Autodesk Fusion 360 part; units mm, degrees
(part 3 of 8)
sketch "Rear removable beam panel | profile (2)" plane through (0, 0, -31) normal (0, 0, 1) x (1, 0, 0) in component "04 | Straight forearm beam"
  line L0 (45, -28) -> (105, -28)
  line L1 (105, -28) -> (108, -25)
  line L2 (108, -25) -> (108, 25)
  line L3 (108, 25) -> (105, 28)
  line L4 (105, 28) -> (45, 28)
  line L5 (45, 28) -> (42, 25)
  line L6 (42, 25) -> (42, -25)
  line L7 (42, -25) -> (45, -28)
  line L8 (55.7, -12) -> (55.725, -12.2536)
  line L9 (55.725, -12.2536) -> (55.799, -12.4975)
  line L10 (55.799, -12.4975) -> (55.9191, -12.7222)
  line L11 (55.9191, -12.7222) -> (56.0808, -12.9192)
  line L12 (56.0808, -12.9192) -> (56.2778, -13.0809)
  line L13 (56.2778, -13.0809) -> (56.5025, -13.201)
  line L14 (56.5025, -13.201) -> (56.7464, -13.275)
  line L15 (56.7464, -13.275) -> (57, -13.3)
  line L16 (57, -13.3) -> (63, -13.3)
  line L17 (63, -13.3) -> (63.2536, -13.275)
  line L18 (63.2536, -13.275) -> (63.4975, -13.201)
  line L19 (63.4975, -13.201) -> (63.7222, -13.0809)
  line L20 (63.7222, -13.0809) -> (63.9192, -12.9192)
  line L21 (63.9192, -12.9192) -> (64.0809, -12.7222)
  line L22 (64.0809, -12.7222) -> (64.201, -12.4975)
  line L23 (64.201, -12.4975) -> (64.275, -12.2536)
  line L24 (64.275, -12.2536) -> (64.3, -12)
  line L25 (64.3, -12) -> (64.275, -11.7464)
  line L26 (64.275, -11.7464) -> (64.201, -11.5025)
  line L27 (64.201, -11.5025) -> (64.0809, -11.2778)
  line L28 (64.0809, -11.2778) -> (63.9192, -11.0808)
  line L29 (63.9192, -11.0808) -> (63.7222, -10.9191)
  line L30 (63.7222, -10.9191) -> (63.4975, -10.799)
  line L31 (63.4975, -10.799) -> (63.2536, -10.725)
  line L32 (63.2536, -10.725) -> (63, -10.7)
  line L33 (63, -10.7) -> (57, -10.7)
  line L34 (57, -10.7) -> (56.7464, -10.725)
  line L35 (56.7464, -10.725) -> (56.5025, -10.799)
  line L36 (56.5025, -10.799) -> (56.2778, -10.9191)
  line L37 (56.2778, -10.9191) -> (56.0808, -11.0808)
  line L38 (56.0808, -11.0808) -> (55.9191, -11.2778)
  line L39 (55.9191, -11.2778) -> (55.799, -11.5025)
  line L40 (55.799, -11.5025) -> (55.725, -11.7464)
  line L41 (55.725, -11.7464) -> (55.7, -12)
  line L42 (55.7, 12) -> (55.725, 11.7464)
  line L43 (55.725, 11.7464) -> (55.799, 11.5025)
  line L44 (55.799, 11.5025) -> (55.9191, 11.2778)
  line L45 (55.9191, 11.2778) -> (56.0808, 11.0808)
  line L46 (56.0808, 11.0808) -> (56.2778, 10.9191)
  line L47 (56.2778, 10.9191) -> (56.5025, 10.799)
  line L48 (56.5025, 10.799) -> (56.7464, 10.725)
  line L49 (56.7464, 10.725) -> (57, 10.7)
  line L50 (57, 10.7) -> (63, 10.7)
  line L51 (63, 10.7) -> (63.2536, 10.725)
  line L52 (63.2536, 10.725) -> (63.4975, 10.799)
  line L53 (63.4975, 10.799) -> (63.7222, 10.9191)
  line L54 (63.7222, 10.9191) -> (63.9192, 11.0808)
  line L55 (63.9192, 11.0808) -> (64.0809, 11.2778)
  line L56 (64.0809, 11.2778) -> (64.201, 11.5025)
  line L57 (64.201, 11.5025) -> (64.275, 11.7464)
  line L58 (64.275, 11.7464) -> (64.3, 12)
  line L59 (64.3, 12) -> (64.275, 12.2536)
  line L60 (64.275, 12.2536) -> (64.201, 12.4975)
  line L61 (64.201, 12.4975) -> (64.0809, 12.7222)
  line L62 (64.0809, 12.7222) -> (63.9192, 12.9192)
  line L63 (63.9192, 12.9192) -> (63.7222, 13.0809)
  line L64 (63.7222, 13.0809) -> (63.4975, 13.201)
  line L65 (63.4975, 13.201) -> (63.2536, 13.275)
  line L66 (63.2536, 13.275) -> (63, 13.3)
  line L67 (63, 13.3) -> (57, 13.3)
  line L68 (57, 13.3) -> (56.7464, 13.275)
  line L69 (56.7464, 13.275) -> (56.5025, 13.201)
  line L70 (56.5025, 13.201) -> (56.2778, 13.0809)
  line L71 (56.2778, 13.0809) -> (56.0808, 12.9192)
  line L72 (56.0808, 12.9192) -> (55.9191, 12.7222)
  line L73 (55.9191, 12.7222) -> (55.799, 12.4975)
  line L74 (55.799, 12.4975) -> (55.725, 12.2536)
  line L75 (55.725, 12.2536) -> (55.7, 12)
  line L76 (64.7, -12) -> (64.725, -12.2536)
  line L77 (64.725, -12.2536) -> (64.799, -12.4975)
  line L78 (64.799, -12.4975) -> (64.9191, -12.7222)
  line L79 (64.9191, -12.7222) -> (65.0808, -12.9192)
  line L80 (65.0808, -12.9192) -> (65.2778, -13.0809)
  line L81 (65.2778, -13.0809) -> (65.5025, -13.201)
  line L82 (65.5025, -13.201) -> (65.7464, -13.275)
  line L83 (65.7464, -13.275) -> (66, -13.3)
  line L84 (66, -13.3) -> (72, -13.3)
  line L85 (72, -13.3) -> (72.2536, -13.275)
  line L86 (72.2536, -13.275) -> (72.4975, -13.201)
  line L87 (72.4975, -13.201) -> (72.7222, -13.0809)
  line L88 (72.7222, -13.0809) -> (72.9192, -12.9192)
  line L89 (72.9192, -12.9192) -> (73.0809, -12.7222)
  line L90 (73.0809, -12.7222) -> (73.201, -12.4975)
  line L91 (73.201, -12.4975) -> (73.275, -12.2536)
  line L92 (73.275, -12.2536) -> (73.3, -12)
  line L93 (73.3, -12) -> (73.275, -11.7464)
  line L94 (73.275, -11.7464) -> (73.201, -11.5025)
  line L95 (73.201, -11.5025) -> (73.0809, -11.2778)
  line L96 (73.0809, -11.2778) -> (72.9192, -11.0808)
  line L97 (72.9192, -11.0808) -> (72.7222, -10.9191)
  line L98 (72.7222, -10.9191) -> (72.4975, -10.799)
  line L99 (72.4975, -10.799) -> (72.2536, -10.725)
  line L100 (72.2536, -10.725) -> (72, -10.7)
  line L101 (72, -10.7) -> (66, -10.7)
  line L102 (66, -10.7) -> (65.7464, -10.725)
  line L103 (65.7464, -10.725) -> (65.5025, -10.799)
  line L104 (65.5025, -10.799) -> (65.2778, -10.9191)
  line L105 (65.2778, -10.9191) -> (65.0808, -11.0808)
  line L106 (65.0808, -11.0808) -> (64.9191, -11.2778)
  line L107 (64.9191, -11.2778) -> (64.799, -11.5025)
  line L108 (64.799, -11.5025) -> (64.725, -11.7464)
  line L109 (64.725, -11.7464) -> (64.7, -12)
  line L110 (64.7, 12) -> (64.725, 11.7464)
  line L111 (64.725, 11.7464) -> (64.799, 11.5025)
  line L112 (64.799, 11.5025) -> (64.9191, 11.2778)
  line L113 (64.9191, 11.2778) -> (65.0808, 11.0808)
  line L114 (65.0808, 11.0808) -> (65.2778, 10.9191)
  line L115 (65.2778, 10.9191) -> (65.5025, 10.799)
  line L116 (65.5025, 10.799) -> (65.7464, 10.725)
  line L117 (65.7464, 10.725) -> (66, 10.7)
  line L118 (66, 10.7) -> (72, 10.7)
  line L119 (72, 10.7) -> (72.2536, 10.725)
  line L120 (72.2536, 10.725) -> (72.4975, 10.799)
  line L121 (72.4975, 10.799) -> (72.7222, 10.9191)
  line L122 (72.7222, 10.9191) -> (72.9192, 11.0808)
  line L123 (72.9192, 11.0808) -> (73.0809, 11.2778)
  line L124 (73.0809, 11.2778) -> (73.201, 11.5025)
  line L125 (73.201, 11.5025) -> (73.275, 11.7464)
  line L126 (73.275, 11.7464) -> (73.3, 12)
  line L127 (73.3, 12) -> (73.275, 12.2536)
  line L128 (73.275, 12.2536) -> (73.201, 12.4975)
  line L129 (73.201, 12.4975) -> (73.0809, 12.7222)
  line L130 (73.0809, 12.7222) -> (72.9192, 12.9192)
  line L131 (72.9192, 12.9192) -> (72.7222, 13.0809)
  line L132 (72.7222, 13.0809) -> (72.4975, 13.201)
  line L133 (72.4975, 13.201) -> (72.2536, 13.275)
  line L134 (72.2536, 13.275) -> (72, 13.3)
  line L135 (72, 13.3) -> (66, 13.3)
  line L136 (66, 13.3) -> (65.7464, 13.275)
  line L137 (65.7464, 13.275) -> (65.5025, 13.201)
  line L138 (65.5025, 13.201) -> (65.2778, 13.0809)
  line L139 (65.2778, 13.0809) -> (65.0808, 12.9192)
  line L140 (65.0808, 12.9192) -> (64.9191, 12.7222)
  line L141 (64.9191, 12.7222) -> (64.799, 12.4975)
  line L142 (64.799, 12.4975) -> (64.725, 12.2536)
  line L143 (64.725, 12.2536) -> (64.7, 12)
  line L144 (73.7, -12) -> (73.725, -12.2536)
  line L145 (73.725, -12.2536) -> (73.799, -12.4975)
  line L146 (73.799, -12.4975) -> (73.9191, -12.7222)
  line L147 (73.9191, -12.7222) -> (74.0808, -12.9192)
  line L148 (74.0808, -12.9192) -> (74.2778, -13.0809)
  line L149 (74.2778, -13.0809) -> (74.5025, -13.201)
  line L150 (74.5025, -13.201) -> (74.7464, -13.275)
  line L151 (74.7464, -13.275) -> (75, -13.3)
  line L152 (75, -13.3) -> (81, -13.3)
  line L153 (81, -13.3) -> (81.2536, -13.275)
  line L154 (81.2536, -13.275) -> (81.4975, -13.201)
  line L155 (81.4975, -13.201) -> (81.7222, -13.0809)
  line L156 (81.7222, -13.0809) -> (81.9192, -12.9192)
  line L157 (81.9192, -12.9192) -> (82.0809, -12.7222)
  line L158 (82.0809, -12.7222) -> (82.201, -12.4975)
  line L159 (82.201, -12.4975) -> (82.275, -12.2536)
  line L160 (82.275, -12.2536) -> (82.3, -12)
  line L161 (82.3, -12) -> (82.275, -11.7464)
  line L162 (82.275, -11.7464) -> (82.201, -11.5025)
  line L163 (82.201, -11.5025) -> (82.0809, -11.2778)
  line L164 (82.0809, -11.2778) -> (81.9192, -11.0808)
  line L165 (81.9192, -11.0808) -> (81.7222, -10.9191)
  line L166 (81.7222, -10.9191) -> (81.4975, -10.799)
  line L167 (81.4975, -10.799) -> (81.2536, -10.725)
  line L168 (81.2536, -10.725) -> (81, -10.7)
  line L169 (81, -10.7) -> (75, -10.7)
  line L170 (75, -10.7) -> (74.7464, -10.725)
  line L171 (74.7464, -10.725) -> (74.5025, -10.799)
  line L172 (74.5025, -10.799) -> (74.2778, -10.9191)
  line L173 (74.2778, -10.9191) -> (74.0808, -11.0808)
  line L174 (74.0808, -11.0808) -> (73.9191, -11.2778)
  line L175 (73.9191, -11.2778) -> (73.799, -11.5025)
  line L176 (73.799, -11.5025) -> (73.725, -11.7464)
  line L177 (73.725, -11.7464) -> (73.7, -12)
  line L178 (73.7, 12) -> (73.725, 11.7464)
  line L179 (73.725, 11.7464) -> (73.799, 11.5025)
  line L180 (73.799, 11.5025) -> (73.9191, 11.2778)
  line L181 (73.9191, 11.2778) -> (74.0808, 11.0808)
  line L182 (74.0808, 11.0808) -> (74.2778, 10.9191)
  line L183 (74.2778, 10.9191) -> (74.5025, 10.799)
  line L184 (74.5025, 10.799) -> (74.7464, 10.725)
  line L185 (74.7464, 10.725) -> (75, 10.7)
  line L186 (75, 10.7) -> (81, 10.7)
  line L187 (81, 10.7) -> (81.2536, 10.725)
  line L188 (81.2536, 10.725) -> (81.4975, 10.799)
  line L189 (81.4975, 10.799) -> (81.7222, 10.9191)
  line L190 (81.7222, 10.9191) -> (81.9192, 11.0808)
  line L191 (81.9192, 11.0808) -> (82.0809, 11.2778)
  line L192 (82.0809, 11.2778) -> (82.201, 11.5025)
  line L193 (82.201, 11.5025) -> (82.275, 11.7464)
  line L194 (82.275, 11.7464) -> (82.3, 12)
  line L195 (82.3, 12) -> (82.275, 12.2536)
  line L196 (82.275, 12.2536) -> (82.201, 12.4975)
  line L197 (82.201, 12.4975) -> (82.0809, 12.7222)
  line L198 (82.0809, 12.7222) -> (81.9192, 12.9192)
  line L199 (81.9192, 12.9192) -> (81.7222, 13.0809)
  line L200 (81.7222, 13.0809) -> (81.4975, 13.201)
  line L201 (81.4975, 13.201) -> (81.2536, 13.275)
  line L202 (81.2536, 13.275) -> (81, 13.3)
  line L203 (81, 13.3) -> (75, 13.3)
  line L204 (75, 13.3) -> (74.7464, 13.275)
  line L205 (74.7464, 13.275) -> (74.5025, 13.201)
  line L206 (74.5025, 13.201) -> (74.2778, 13.0809)
  line L207 (74.2778, 13.0809) -> (74.0808, 12.9192)
  line L208 (74.0808, 12.9192) -> (73.9191, 12.7222)
  line L209 (73.9191, 12.7222) -> (73.799, 12.4975)
  line L210 (73.799, 12.4975) -> (73.725, 12.2536)
  line L211 (73.725, 12.2536) -> (73.7, 12)
extrude "Rear removable beam panel'" add sketch "Rear removable beam panel | profile (2)" along normal blind 2.5 separate body makes body 95 in component "04 | Straight forearm beam"
ref_plane "WorkPlane4" through (0, 0, 39.5) normal (0, 0, 1) x (1, 0, 0) in component "04 | Straight forearm beam"
sketch "Front removable beam panel | profile (2)" plane through (0, 0, 39.5) normal (0, 0, 1) x (1, 0, 0) in component "04 | Straight forearm beam"
  line L0 (45, -28) -> (105, -28)
  line L1 (105, -28) -> (108, -25)
  line L2 (108, -25) -> (108, 25)
  line L3 (108, 25) -> (105, 28)
  line L4 (105, 28) -> (45, 28)
  line L5 (45, 28) -> (42, 25)
  line L6 (42, 25) -> (42, -25)
  line L7 (42, -25) -> (45, -28)
extrude "Front removable beam panel'" add sketch "Front removable beam panel | profile (2)" along normal blind 2.5 separate body makes body 96 in component "04 | Straight forearm beam"
ref_plane "WorkPlane5" through (0, 0, 14) normal (0, 0, 1) x (1, 0, 0) in component "04 | Straight forearm beam"
sketch "Motor mount | metal, stock and holes to finalize | profile (4)" plane through (0, 0, 14) normal (0, 0, 1) x (1, 0, 0) in component "04 | Straight forearm beam"
  line L0 (46.35, -23.65) -> (91.65, -23.65)
  line L1 (91.65, -23.65) -> (92.65, -22.65)
  line L2 (92.65, -22.65) -> (92.65, 22.65)
  line L3 (92.65, 22.65) -> (91.65, 23.65)
  line L4 (91.65, 23.65) -> (46.35, 23.65)
  line L5 (46.35, 23.65) -> (45.35, 22.65)
  line L6 (45.35, 22.65) -> (45.35, -22.65)
  line L7 (45.35, -22.65) -> (46.35, -23.65)
  circle A0 centre (69, 0) radius 11.2
  circle A1 centre (53.5, -15.5) radius 1.6
  circle A2 centre (53.5, 15.5) radius 1.6
  circle A3 centre (84.5, -15.5) radius 1.6
  circle A4 centre (84.5, 15.5) radius 1.6
extrude "Motor mount | metal, stock and holes to finalize'''" add sketch "Motor mount | metal, stock and holes to finalize | profile (4)" along normal blind 3 separate body makes body 97 in component "04 | Straight forearm beam"
ref_plane "WorkPlane6" through (0, 0, -36) normal (0, 0, 1) x (1, 0, 0) in component "04 | Straight forearm beam"
sketch "Proximal bearing cheek | profile (2)" plane through (0, 0, -36) normal (0, 0, 1) x (1, 0, 0) in component "04 | Straight forearm beam"
  line L0 (-40, 0) -> (-39.6578, -5.221)
  line L1 (-39.6578, -5.221) -> (-38.637, -10.3528)
  line L2 (-38.637, -10.3528) -> (-36.9552, -15.3073)
  line L3 (-36.9552, -15.3073) -> (-34.641, -20)
  line L4 (-34.641, -20) -> (-31.7341, -24.3505)
  line L5 (-31.7341, -24.3505) -> (-28.2843, -28.2843)
  line L6 (-28.2843, -28.2843) -> (-24.3505, -31.7341)
  line L7 (-24.3505, -31.7341) -> (-20, -34.641)
  line L8 (-20, -34.641) -> (-15.3073, -36.9552)
  line L9 (-15.3073, -36.9552) -> (-10.3528, -38.637)
  line L10 (-10.3528, -38.637) -> (-5.221, -39.6578)
  line L11 (-5.221, -39.6578) -> (0, -40)
  line L12 (0, -40) -> (5.221, -39.6578)
  line L13 (5.221, -39.6578) -> (10.3528, -38.637)
  line L14 (10.3528, -38.637) -> (59, -23)
  line L15 (59, -23) -> (59, 23)
  line L16 (59, 23) -> (10.3528, 38.637)
  line L17 (10.3528, 38.637) -> (5.221, 39.6578)
  line L18 (5.221, 39.6578) -> (0, 40)
  line L19 (0, 40) -> (-5.221, 39.6578)
  line L20 (-5.221, 39.6578) -> (-10.3528, 38.637)
  line L21 (-10.3528, 38.637) -> (-15.3073, 36.9552)
  line L22 (-15.3073, 36.9552) -> (-20, 34.641)
  line L23 (-20, 34.641) -> (-24.3505, 31.7341)
  line L24 (-24.3505, 31.7341) -> (-28.2843, 28.2843)
  line L25 (-28.2843, 28.2843) -> (-31.7341, 24.3505)
  line L26 (-31.7341, 24.3505) -> (-34.641, 20)
  line L27 (-34.641, 20) -> (-36.9552, 15.3073)
  line L28 (-36.9552, 15.3073) -> (-38.637, 10.3528)
  line L29 (-38.637, 10.3528) -> (-39.6578, 5.221)
  line L30 (-39.6578, 5.221) -> (-40, 0)
  circle A0 centre (0, 0) radius 15.15
extrude "Proximal bearing cheek'" add sketch "Proximal bearing cheek | profile (2)" along normal blind 5 separate body makes body 98 in component "04 | Straight forearm beam"
ref_plane "WorkPlane7" through (0, 0, 42) normal (0, 0, 1) x (1, 0, 0) in component "04 | Straight forearm beam"
sketch "Proximal bearing cheek | profile (1) (2)" plane through (0, 0, 42) normal (0, 0, 1) x (1, 0, 0) in component "04 | Straight forearm beam"
  line L0 (-40, 0) -> (-39.6578, -5.221)
  line L1 (-39.6578, -5.221) -> (-38.637, -10.3528)
  line L2 (-38.637, -10.3528) -> (-36.9552, -15.3073)
  line L3 (-36.9552, -15.3073) -> (-34.641, -20)
  line L4 (-34.641, -20) -> (-31.7341, -24.3505)
  line L5 (-31.7341, -24.3505) -> (-28.2843, -28.2843)
  line L6 (-28.2843, -28.2843) -> (-24.3505, -31.7341)
  line L7 (-24.3505, -31.7341) -> (-20, -34.641)
  line L8 (-20, -34.641) -> (-15.3073, -36.9552)
  line L9 (-15.3073, -36.9552) -> (-10.3528, -38.637)
  line L10 (-10.3528, -38.637) -> (-5.221, -39.6578)
  line L11 (-5.221, -39.6578) -> (0, -40)
  line L12 (0, -40) -> (5.221, -39.6578)
  line L13 (5.221, -39.6578) -> (10.3528, -38.637)
  line L14 (10.3528, -38.637) -> (59, -23)
  line L15 (59, -23) -> (59, 23)
  line L16 (59, 23) -> (10.3528, 38.637)
  line L17 (10.3528, 38.637) -> (5.221, 39.6578)
  line L18 (5.221, 39.6578) -> (0, 40)
  line L19 (0, 40) -> (-5.221, 39.6578)
  line L20 (-5.221, 39.6578) -> (-10.3528, 38.637)
  line L21 (-10.3528, 38.637) -> (-15.3073, 36.9552)
  line L22 (-15.3073, 36.9552) -> (-20, 34.641)
  line L23 (-20, 34.641) -> (-24.3505, 31.7341)
  line L24 (-24.3505, 31.7341) -> (-28.2843, 28.2843)
  line L25 (-28.2843, 28.2843) -> (-31.7341, 24.3505)
  line L26 (-31.7341, 24.3505) -> (-34.641, 20)
  line L27 (-34.641, 20) -> (-36.9552, 15.3073)
  line L28 (-36.9552, 15.3073) -> (-38.637, 10.3528)
  line L29 (-38.637, 10.3528) -> (-39.6578, 5.221)
  line L30 (-39.6578, 5.221) -> (-40, 0)
  circle A0 centre (0, 0) radius 15.15
extrude "Proximal bearing cheek (1)'" add sketch "Proximal bearing cheek | profile (1) (2)" along normal blind 5 separate body makes body 99 in component "04 | Straight forearm beam"
ref_plane "WorkPlane8" through (0, 0, 20) normal (0, 0, 1) x (1, 0, 0) in component "04 | Straight forearm beam"
sketch "20T pulley envelope | tooth profile pending | profile (4)" plane through (0, 0, 20) normal (0, 0, 1) x (1, 0, 0) in component "04 | Straight forearm beam"
  circle A0 centre (69, 0) radius 6.9662
  circle A1 centre (69, 0) radius 2.5
extrude "20T pulley envelope | tooth profile pending'''" add sketch "20T pulley envelope | tooth profile pending | profile (4)" along normal blind 6 separate body makes body 100 in component "04 | Straight forearm beam"
ref_plane "WorkPlane9" through (0, 0, 26) normal (0, 0, 1) x (1, 0, 0) in component "04 | Straight forearm beam"
sketch "20T flange | profile (4)" plane through (0, 0, 26) normal (0, 0, 1) x (1, 0, 0) in component "04 | Straight forearm beam"
  circle A0 centre (69, 0) radius 7.3662
  circle A1 centre (69, 0) radius 2.5
extrude "20T flange'''" add sketch "20T flange | profile (4)" along normal blind 0.8 separate body makes body 101 in component "04 | Straight forearm beam"
ref_plane "WorkPlane10" through (0, 0, 20) normal (0, 0, 1) x (1, 0, 0) in component "04 | Straight forearm beam"
sketch "80T pulley envelope | tooth profile pending | profile" plane through (0, 0, 20) normal (0, 0, 1) x (1, 0, 0) in component "04 | Straight forearm beam"
  circle A0 centre (155, 0) radius 26.0648
  circle A1 centre (155, 0) radius 6
extrude "80T pulley envelope | tooth profile pending" add sketch "80T pulley envelope | tooth profile pending | profile" along normal blind 6 separate body makes body 102 in component "04 | Straight forearm beam"
ref_plane "WorkPlane11" through (0, 0, 26) normal (0, 0, 1) x (1, 0, 0) in component "04 | Straight forearm beam"
sketch "80T flange | profile" plane through (0, 0, 26) normal (0, 0, 1) x (1, 0, 0) in component "04 | Straight forearm beam"
  circle A0 centre (155, 0) radius 26.4648
  circle A1 centre (155, 0) radius 6
extrude "80T flange" add sketch "80T flange | profile" along normal blind 0.8 separate body makes body 103 in component "04 | Straight forearm beam"
ref_plane "WorkPlane12" through (0, 0, 20) normal (0, 0, 1) x (1, 0, 0) in component "04 | Straight forearm beam"
sketch "Internal 4:1 span | belt length pending | profile" plane through (0, 0, 20) normal (0, 0, 1) x (1, 0, 0) in component "04 | Straight forearm beam"
  line L0 (67.4419, 6.841) -> (149.2005, 25.4627)
  line L1 (149.2005, 25.4627) -> (149.4892, 24.1951)
  line L2 (149.4892, 24.1951) -> (67.7306, 5.5735)
  line L3 (67.7306, 5.5735) -> (67.4419, 6.841)
extrude "Internal 4:1 span | belt length pending" add sketch "Internal 4:1 span | belt length pending | profile" along normal blind 6 separate body makes body 104 in component "04 | Straight forearm beam"
ref_plane "WorkPlane13" through (0, 0, 20) normal (0, 0, 1) x (1, 0, 0) in component "04 | Straight forearm beam"
sketch "Internal 4:1 span | belt length pending | profile (1)" plane through (0, 0, 20) normal (0, 0, 1) x (1, 0, 0) in component "04 | Straight forearm beam"
  line L0 (67.7306, -5.5735) -> (149.4892, -24.1951)
  line L1 (149.4892, -24.1951) -> (149.2005, -25.4627)
  line L2 (149.2005, -25.4627) -> (67.4419, -6.841)
  line L3 (67.4419, -6.841) -> (67.7306, -5.5735)
extrude "Internal 4:1 span | belt length pending (1)" add sketch "Internal 4:1 span | belt length pending | profile (1)" along normal blind 6 separate body makes body 105 in component "04 | Straight forearm beam"
ref_plane "WorkPlane14" through (0, 0, 20) normal (0, 0, 1) x (1, 0, 0) in component "04 | Straight forearm beam"
sketch "Internal 4:1 drive wrap | profile" plane through (0, 0, 20) normal (0, 0, 1) x (1, 0, 0) in component "04 | Straight forearm beam"
  circle A0 centre (69, 0) radius 7.0162
  circle A1 centre (69, 0) radius 5.7162
extrude "Internal 4:1 drive wrap" add sketch "Internal 4:1 drive wrap | profile" along normal blind 6 separate body makes body 106 in component "04 | Straight forearm beam"
ref_plane "WorkPlane15" through (0, 0, 20) normal (0, 0, 1) x (1, 0, 0) in component "04 | Straight forearm beam"
sketch "Internal 4:1 driven wrap | profile" plane through (0, 0, 20) normal (0, 0, 1) x (1, 0, 0) in component "04 | Straight forearm beam"
  circle A0 centre (155, 0) radius 26.1148
  circle A1 centre (155, 0) radius 24.8148
extrude "Internal 4:1 driven wrap" add sketch "Internal 4:1 driven wrap | profile" along normal blind 6 separate body makes body 107 in component "04 | Straight forearm beam"
ref_plane "WorkPlane16" through (0, 0, -36) normal (0, 0, 1) x (1, 0, 0) in component "04 | Straight forearm beam"
sketch "Distal flat fork cheek | profile (2)" plane through (0, 0, -36) normal (0, 0, 1) x (1, 0, 0) in component "04 | Straight forearm beam"
  line L0 (98, -23) -> (150.8232, -31.7262)
  line L1 (150.8232, -31.7262) -> (155, -32)
  line L2 (155, -32) -> (159.1768, -31.7262)
  line L3 (159.1768, -31.7262) -> (163.2822, -30.9096)
  line L4 (163.2822, -30.9096) -> (167.2459, -29.5641)
  line L5 (167.2459, -29.5641) -> (171, -27.7128)
  line L6 (171, -27.7128) -> (174.4804, -25.3873)
  line L7 (174.4804, -25.3873) -> (177.6274, -22.6274)
  line L8 (177.6274, -22.6274) -> (180.3873, -19.4804)
  line L9 (180.3873, -19.4804) -> (182.7128, -16)
  line L10 (182.7128, -16) -> (184.5641, -12.2459)
  line L11 (184.5641, -12.2459) -> (185.9096, -8.2822)
  line L12 (185.9096, -8.2822) -> (186.7262, -4.1768)
  line L13 (186.7262, -4.1768) -> (187, 0)
  line L14 (187, 0) -> (186.7262, 4.1768)
  line L15 (186.7262, 4.1768) -> (185.9096, 8.2822)
  line L16 (185.9096, 8.2822) -> (184.5641, 12.2459)
  line L17 (184.5641, 12.2459) -> (182.7128, 16)
  line L18 (182.7128, 16) -> (180.3873, 19.4804)
  line L19 (180.3873, 19.4804) -> (177.6274, 22.6274)
  line L20 (177.6274, 22.6274) -> (174.4804, 25.3873)
  line L21 (174.4804, 25.3873) -> (171, 27.7128)
  line L22 (171, 27.7128) -> (167.2459, 29.5641)
  line L23 (167.2459, 29.5641) -> (163.2822, 30.9096)
  line L24 (163.2822, 30.9096) -> (159.1768, 31.7262)
  line L25 (159.1768, 31.7262) -> (155, 32)
  line L26 (155, 32) -> (150.8232, 31.7262)
  line L27 (150.8232, 31.7262) -> (98, 23)
  line L28 (98, 23) -> (98, -23)
  circle A0 centre (155, 0) radius 15.2
extrude "Distal flat fork cheek'" add sketch "Distal flat fork cheek | profile (2)" along normal blind 5 separate body makes body 108 in component "04 | Straight forearm beam"
ref_plane "WorkPlane17" through (0, 0, 42) normal (0, 0, 1) x (1, 0, 0) in component "04 | Straight forearm beam"
sketch "Distal flat fork cheek | profile (1) (2)" plane through (0, 0, 42) normal (0, 0, 1) x (1, 0, 0) in component "04 | Straight forearm beam"
  line L0 (98, -23) -> (150.8232, -31.7262)
  line L1 (150.8232, -31.7262) -> (155, -32)
  line L2 (155, -32) -> (159.1768, -31.7262)
  line L3 (159.1768, -31.7262) -> (163.2822, -30.9096)
  line L4 (163.2822, -30.9096) -> (167.2459, -29.5641)
  line L5 (167.2459, -29.5641) -> (171, -27.7128)
  line L6 (171, -27.7128) -> (174.4804, -25.3873)
  line L7 (174.4804, -25.3873) -> (177.6274, -22.6274)
  line L8 (177.6274, -22.6274) -> (180.3873, -19.4804)
  line L9 (180.3873, -19.4804) -> (182.7128, -16)
  line L10 (182.7128, -16) -> (184.5641, -12.2459)
  line L11 (184.5641, -12.2459) -> (185.9096, -8.2822)
  line L12 (185.9096, -8.2822) -> (186.7262, -4.1768)
  line L13 (186.7262, -4.1768) -> (187, 0)
  line L14 (187, 0) -> (186.7262, 4.1768)
  line L15 (186.7262, 4.1768) -> (185.9096, 8.2822)
  line L16 (185.9096, 8.2822) -> (184.5641, 12.2459)
  line L17 (184.5641, 12.2459) -> (182.7128, 16)
  line L18 (182.7128, 16) -> (180.3873, 19.4804)
  line L19 (180.3873, 19.4804) -> (177.6274, 22.6274)
  line L20 (177.6274, 22.6274) -> (174.4804, 25.3873)
  line L21 (174.4804, 25.3873) -> (171, 27.7128)
  line L22 (171, 27.7128) -> (167.2459, 29.5641)
  line L23 (167.2459, 29.5641) -> (163.2822, 30.9096)
  line L24 (163.2822, 30.9096) -> (159.1768, 31.7262)
  line L25 (159.1768, 31.7262) -> (155, 32)
  line L26 (155, 32) -> (150.8232, 31.7262)
  line L27 (150.8232, 31.7262) -> (98, 23)
  line L28 (98, 23) -> (98, -23)
  circle A0 centre (155, 0) radius 15.2
extrude "Distal flat fork cheek (1)'" add sketch "Distal flat fork cheek | profile (1) (2)" along normal blind 5 separate body makes body 109 in component "04 | Straight forearm beam"
ref_plane "WorkPlane18" through (0, 0, 47.3) normal (0, 0, 1) x (1, 0, 0) in component "04 | Straight forearm beam"
sketch "Wrist recessed graphite seam | profile" plane through (0, 0, 47.3) normal (0, 0, 1) x (1, 0, 0) in component "04 | Straight forearm beam"
  circle A0 centre (155, 0) radius 31
extrude "Wrist recessed graphite seam" add sketch "Wrist recessed graphite seam | profile" along normal blind 0.7 separate body makes body 110 in component "04 | Straight forearm beam"
ref_plane "WorkPlane19" through (0, 0, 48) normal (0, 0, 1) x (1, 0, 0) in component "04 | Straight forearm beam"
sketch "Wrist narrow white annulus | profile" plane through (0, 0, 48) normal (0, 0, 1) x (1, 0, 0) in component "04 | Straight forearm beam"
  circle A0 centre (155, 0) radius 30.7
  circle A1 centre (155, 0) radius 29.3
extrude "Wrist narrow white annulus" add sketch "Wrist narrow white annulus | profile" along normal blind 1.3 separate body makes body 111 in component "04 | Straight forearm beam"
ref_plane "WorkPlane20" through (0, 0, 48) normal (0, 0, 1) x (1, 0, 0) in component "04 | Straight forearm beam"
sketch "Wrist flat Green Marble face | profile" plane through (0, 0, 48) normal (0, 0, 1) x (1, 0, 0) in component "04 | Straight forearm beam"
  line L0 (184, 0) -> (183.8604, 2.8425)
  line L1 (183.8604, 2.8425) -> (183.4428, 5.6576)
  line L2 (183.4428, 5.6576) -> (182.7513, 8.4183)
  line L3 (182.7513, 8.4183) -> (181.7925, 11.0978)
  line L4 (181.7925, 11.0978) -> (180.5757, 13.6705)
  line L5 (180.5757, 13.6705) -> (179.1126, 16.1115)
  line L6 (179.1126, 16.1115) -> (177.4173, 18.3974)
  line L7 (177.4173, 18.3974) -> (175.5061, 20.5061)
  line L8 (175.5061, 20.5061) -> (173.3974, 22.4173)
  line L9 (173.3974, 22.4173) -> (171.1115, 24.1126)
  line L10 (171.1115, 24.1126) -> (168.6705, 25.5757)
  line L11 (168.6705, 25.5757) -> (166.0978, 26.7925)
  line L12 (166.0978, 26.7925) -> (163.4183, 27.7513)
  line L13 (163.4183, 27.7513) -> (160.6576, 28.4428)
  line L14 (160.6576, 28.4428) -> (157.8425, 28.8604)
  line L15 (157.8425, 28.8604) -> (155, 29)
  line L16 (155, 29) -> (152.1575, 28.8604)
  line L17 (152.1575, 28.8604) -> (149.3424, 28.4428)
  line L18 (149.3424, 28.4428) -> (146.5817, 27.7513)
  line L19 (146.5817, 27.7513) -> (143.9022, 26.7925)
  line L20 (143.9022, 26.7925) -> (141.3295, 25.5757)
  line L21 (141.3295, 25.5757) -> (138.8885, 24.1126)
  line L22 (138.8885, 24.1126) -> (136.6026, 22.4173)
  line L23 (136.6026, 22.4173) -> (134.4939, 20.5061)
  line L24 (134.4939, 20.5061) -> (132.5827, 18.3974)
  line L25 (132.5827, 18.3974) -> (130.8874, 16.1115)
  line L26 (130.8874, 16.1115) -> (129.4243, 13.6705)
  line L27 (129.4243, 13.6705) -> (128.2075, 11.0978)
  line L28 (128.2075, 11.0978) -> (127.2487, 8.4183)
  line L29 (127.2487, 8.4183) -> (126.5572, 5.6576)
  line L30 (126.5572, 5.6576) -> (126.1396, 2.8425)
  line L31 (126.1396, 2.8425) -> (126, 0)
  line L32 (126, 0) -> (126.1396, -2.8425)
  line L33 (126.1396, -2.8425) -> (126.5572, -5.6576)
  line L34 (126.5572, -5.6576) -> (127.2487, -8.4183)
  line L35 (127.2487, -8.4183) -> (128.2075, -11.0978)
  line L36 (128.2075, -11.0978) -> (129.4243, -13.6705)
  line L37 (129.4243, -13.6705) -> (130.8874, -16.1115)
  line L38 (130.8874, -16.1115) -> (132.5827, -18.3974)
  line L39 (132.5827, -18.3974) -> (134.4939, -20.5061)
  line L40 (134.4939, -20.5061) -> (136.6026, -22.4173)
  line L41 (136.6026, -22.4173) -> (138.8885, -24.1126)
  line L42 (138.8885, -24.1126) -> (141.3295, -25.5757)
  line L43 (141.3295, -25.5757) -> (143.9022, -26.7925)
  line L44 (143.9022, -26.7925) -> (146.5817, -27.7513)
  line L45 (146.5817, -27.7513) -> (149.3424, -28.4428)
  line L46 (149.3424, -28.4428) -> (152.1575, -28.8604)
  line L47 (152.1575, -28.8604) -> (155, -29)
  line L48 (155, -29) -> (157.8425, -28.8604)
  line L49 (157.8425, -28.8604) -> (160.6576, -28.4428)
  line L50 (160.6576, -28.4428) -> (163.4183, -27.7513)
  line L51 (163.4183, -27.7513) -> (166.0978, -26.7925)
  line L52 (166.0978, -26.7925) -> (168.6705, -25.5757)
  line L53 (168.6705, -25.5757) -> (171.1115, -24.1126)
  line L54 (171.1115, -24.1126) -> (173.3974, -22.4173)
  line L55 (173.3974, -22.4173) -> (175.5061, -20.5061)
  line L56 (175.5061, -20.5061) -> (177.4173, -18.3974)
  line L57 (177.4173, -18.3974) -> (179.1126, -16.1115)
  line L58 (179.1126, -16.1115) -> (180.5757, -13.6705)
  line L59 (180.5757, -13.6705) -> (181.7925, -11.0978)
  line L60 (181.7925, -11.0978) -> (182.7513, -8.4183)
  line L61 (182.7513, -8.4183) -> (183.4428, -5.6576)
  line L62 (183.4428, -5.6576) -> (183.8604, -2.8425)
  line L63 (183.8604, -2.8425) -> (184, 0)
  circle A0 centre (179, 0) radius 1.65
  circle A1 centre (167, 20.7846) radius 1.65
  circle A2 centre (143, 20.7846) radius 1.65
  circle A3 centre (131, 0) radius 1.65
  circle A4 centre (143, -20.7846) radius 1.65
  circle A5 centre (167, -20.7846) radius 1.65
extrude "Wrist flat Green Marble face" add sketch "Wrist flat Green Marble face | profile" along normal blind 1.4 separate body makes body 112 in component "04 | Straight forearm beam"
ref_plane "WorkPlane21" through (0, 0, 49.45) normal (0, 0, 1) x (1, 0, 0) in component "04 | Straight forearm beam"
sketch "Wrist flush M3 head | profile" plane through (0, 0, 49.45) normal (0, 0, 1) x (1, 0, 0) in component "04 | Straight forearm beam"
  line L0 (180.9486, 1.125) -> (179, 2.25)
  line L1 (179, 2.25) -> (177.0514, 1.125)
  line L2 (177.0514, 1.125) -> (177.0514, -1.125)
  line L3 (177.0514, -1.125) -> (179, -2.25)
  line L4 (179, -2.25) -> (180.9486, -1.125)
  line L5 (180.9486, -1.125) -> (180.9486, 1.125)
  circle A0 centre (179, 0) radius 0.9
extrude "Wrist flush M3 head" add sketch "Wrist flush M3 head | profile" along normal blind 0.6 separate body makes body 113 in component "04 | Straight forearm beam"
ref_plane "WorkPlane22" through (0, 0, 49.45) normal (0, 0, 1) x (1, 0, 0) in component "04 | Straight forearm beam"
sketch "Wrist flush M3 head | profile (1)" plane through (0, 0, 49.45) normal (0, 0, 1) x (1, 0, 0) in component "04 | Straight forearm beam"
  line L0 (168.9486, 21.9096) -> (167, 23.0346)
  line L1 (167, 23.0346) -> (165.0514, 21.9096)
  line L2 (165.0514, 21.9096) -> (165.0514, 19.6596)
  line L3 (165.0514, 19.6596) -> (167, 18.5346)
  line L4 (167, 18.5346) -> (168.9486, 19.6596)
  line L5 (168.9486, 19.6596) -> (168.9486, 21.9096)
  circle A0 centre (167, 20.7846) radius 0.9
extrude "Wrist flush M3 head (1)" add sketch "Wrist flush M3 head | profile (1)" along normal blind 0.6 separate body makes body 114 in component "04 | Straight forearm beam"
ref_plane "WorkPlane23" through (0, 0, 49.45) normal (0, 0, 1) x (1, 0, 0) in component "04 | Straight forearm beam"
sketch "Wrist flush M3 head | profile (2)" plane through (0, 0, 49.45) normal (0, 0, 1) x (1, 0, 0) in component "04 | Straight forearm beam"
  line L0 (144.9486, 21.9096) -> (143, 23.0346)
  line L1 (143, 23.0346) -> (141.0514, 21.9096)
  line L2 (141.0514, 21.9096) -> (141.0514, 19.6596)
  line L3 (141.0514, 19.6596) -> (143, 18.5346)
  line L4 (143, 18.5346) -> (144.9486, 19.6596)
  line L5 (144.9486, 19.6596) -> (144.9486, 21.9096)
  circle A0 centre (143, 20.7846) radius 0.9
extrude "Wrist flush M3 head (2)" add sketch "Wrist flush M3 head | profile (2)" along normal blind 0.6 separate body makes body 115 in component "04 | Straight forearm beam"
ref_plane "WorkPlane24" through (0, 0, 49.45) normal (0, 0, 1) x (1, 0, 0) in component "04 | Straight forearm beam"
sketch "Wrist flush M3 head | profile (3)" plane through (0, 0, 49.45) normal (0, 0, 1) x (1, 0, 0) in component "04 | Straight forearm beam"
  line L0 (132.9486, 1.125) -> (131, 2.25)
  line L1 (131, 2.25) -> (129.0514, 1.125)
  line L2 (129.0514, 1.125) -> (129.0514, -1.125)
  line L3 (129.0514, -1.125) -> (131, -2.25)
  line L4 (131, -2.25) -> (132.9486, -1.125)
  line L5 (132.9486, -1.125) -> (132.9486, 1.125)
  circle A0 centre (131, 0) radius 0.9
extrude "Wrist flush M3 head (3)" add sketch "Wrist flush M3 head | profile (3)" along normal blind 0.6 separate body makes body 116 in component "04 | Straight forearm beam"
ref_plane "WorkPlane25" through (0, 0, 49.45) normal (0, 0, 1) x (1, 0, 0) in component "04 | Straight forearm beam"
sketch "Wrist flush M3 head | profile (4)" plane through (0, 0, 49.45) normal (0, 0, 1) x (1, 0, 0) in component "04 | Straight forearm beam"
  line L0 (144.9486, -19.6596) -> (143, -18.5346)
  line L1 (143, -18.5346) -> (141.0514, -19.6596)
  line L2 (141.0514, -19.6596) -> (141.0514, -21.9096)
  line L3 (141.0514, -21.9096) -> (143, -23.0346)
  line L4 (143, -23.0346) -> (144.9486, -21.9096)
  line L5 (144.9486, -21.9096) -> (144.9486, -19.6596)
  circle A0 centre (143, -20.7846) radius 0.9
extrude "Wrist flush M3 head (4)" add sketch "Wrist flush M3 head | profile (4)" along normal blind 0.6 separate body makes body 117 in component "04 | Straight forearm beam"
ref_plane "WorkPlane26" through (0, 0, 49.45) normal (0, 0, 1) x (1, 0, 0) in component "04 | Straight forearm beam"
sketch "Wrist flush M3 head | profile (5)" plane through (0, 0, 49.45) normal (0, 0, 1) x (1, 0, 0) in component "04 | Straight forearm beam"
  line L0 (168.9486, -19.6596) -> (167, -18.5346)
  line L1 (167, -18.5346) -> (165.0514, -19.6596)
  line L2 (165.0514, -19.6596) -> (165.0514, -21.9096)
  line L3 (165.0514, -21.9096) -> (167, -23.0346)
  line L4 (167, -23.0346) -> (168.9486, -21.9096)
  line L5 (168.9486, -21.9096) -> (168.9486, -19.6596)
  circle A0 centre (167, -20.7846) radius 0.9
extrude "Wrist flush M3 head (5)" add sketch "Wrist flush M3 head | profile (5)" along normal blind 0.6 separate body makes body 118 in component "04 | Straight forearm beam"
ref_plane "WorkPlane27" through (0, 0, 42.15) normal (0, 0, 1) x (1, 0, 0) in component "04 | Straight forearm beam"
sketch "Thin white longitudinal rail | profile (2)" plane through (0, 0, 42.15) normal (0, 0, 1) x (1, 0, 0) in component "04 | Straight forearm beam"
  line L0 (46.6, -26.2) -> (103.4, -26.2)
  line L1 (103.4, -26.2) -> (104, -25.6)
  line L2 (104, -25.6) -> (104, -24.4)
  line L3 (104, -24.4) -> (103.4, -23.8)
  line L4 (103.4, -23.8) -> (46.6, -23.8)
  line L5 (46.6, -23.8) -> (46, -24.4)
  line L6 (46, -24.4) -> (46, -25.6)
  line L7 (46, -25.6) -> (46.6, -26.2)
extrude "Thin white longitudinal rail'" add sketch "Thin white longitudinal rail | profile (2)" along normal blind 1.1 separate body makes body 119 in component "04 | Straight forearm beam"
ref_plane "WorkPlane28" through (0, 0, 42) normal (0, 0, 1) x (1, 0, 0) in component "04 | Straight forearm beam"
sketch "Beam service fastener | profile (4)" plane through (0, 0, 42) normal (0, 0, 1) x (1, 0, 0) in component "04 | Straight forearm beam"
  line L0 (50.8187, -19.95) -> (49, -18.9)
  line L1 (49, -18.9) -> (47.1813, -19.95)
  line L2 (47.1813, -19.95) -> (47.1813, -22.05)
  line L3 (47.1813, -22.05) -> (49, -23.1)
  line L4 (49, -23.1) -> (50.8187, -22.05)
  line L5 (50.8187, -22.05) -> (50.8187, -19.95)
  circle A0 centre (49, -21) radius 0.9
extrude "Beam service fastener'" add sketch "Beam service fastener | profile (4)" along normal blind 1 separate body makes body 120 in component "04 | Straight forearm beam"
ref_plane "WorkPlane29" through (0, 0, 42) normal (0, 0, 1) x (1, 0, 0) in component "04 | Straight forearm beam"
sketch "Beam service fastener | profile (1) (2)" plane through (0, 0, 42) normal (0, 0, 1) x (1, 0, 0) in component "04 | Straight forearm beam"
  line L0 (50.8187, 22.05) -> (49, 23.1)
  line L1 (49, 23.1) -> (47.1813, 22.05)
  line L2 (47.1813, 22.05) -> (47.1813, 19.95)
  line L3 (47.1813, 19.95) -> (49, 18.9)
  line L4 (49, 18.9) -> (50.8187, 19.95)
  line L5 (50.8187, 19.95) -> (50.8187, 22.05)
  circle A0 centre (49, 21) radius 0.9
extrude "Beam service fastener (1)'" add sketch "Beam service fastener | profile (1) (2)" along normal blind 1 separate body makes body 121 in component "04 | Straight forearm beam"
ref_plane "WorkPlane30" through (0, 0, 42) normal (0, 0, 1) x (1, 0, 0) in component "04 | Straight forearm beam"
sketch "Beam service fastener | profile (2) (2)" plane through (0, 0, 42) normal (0, 0, 1) x (1, 0, 0) in component "04 | Straight forearm beam"
  line L0 (102.8187, -19.95) -> (101, -18.9)
  line L1 (101, -18.9) -> (99.1813, -19.95)
  line L2 (99.1813, -19.95) -> (99.1813, -22.05)
  line L3 (99.1813, -22.05) -> (101, -23.1)
  line L4 (101, -23.1) -> (102.8187, -22.05)
  line L5 (102.8187, -22.05) -> (102.8187, -19.95)
  circle A0 centre (101, -21) radius 0.9
extrude "Beam service fastener (2)'" add sketch "Beam service fastener | profile (2) (2)" along normal blind 1 separate body makes body 122 in component "04 | Straight forearm beam"
ref_plane "WorkPlane31" through (0, 0, 42) normal (0, 0, 1) x (1, 0, 0) in component "04 | Straight forearm beam"
sketch "Beam service fastener | profile (3) (2)" plane through (0, 0, 42) normal (0, 0, 1) x (1, 0, 0) in component "04 | Straight forearm beam"
  line L0 (102.8187, 22.05) -> (101, 23.1)
  line L1 (101, 23.1) -> (99.1813, 22.05)
  line L2 (99.1813, 22.05) -> (99.1813, 19.95)
  line L3 (99.1813, 19.95) -> (101, 18.9)
  line L4 (101, 18.9) -> (102.8187, 19.95)
  line L5 (102.8187, 19.95) -> (102.8187, 22.05)
  circle A0 centre (101, 21) radius 0.9
extrude "Beam service fastener (3)'" add sketch "Beam service fastener | profile (3) (2)" along normal blind 1 separate body makes body 123 in component "04 | Straight forearm beam"
ref_plane "WorkPlane32" through (0, 0, -31) normal (0, 0, 1) x (1, 0, 0) in component "04 | Straight forearm beam"
sketch "Output coupling sleeve | fastener detail pending | profile (2)" plane through (0, 0, -31) normal (0, 0, 1) x (1, 0, 0) in component "04 | Straight forearm beam"
  circle A0 centre (0, 0) radius 15
  circle A1 centre (0, 0) radius 9
extrude "Output coupling sleeve | fastener detail pending'" add sketch "Output coupling sleeve | fastener detail pending | profile (2)" along normal blind 7 separate body makes body 124 in component "04 | Straight forearm beam"
ref_plane "WorkPlane33" through (0, 0, 24) normal (0, 0, 1) x (1, 0, 0) in component "04 | Straight forearm beam"
sketch "Output coupling sleeve | fastener detail pending | profile (1) (2)" plane through (0, 0, 24) normal (0, 0, 1) x (1, 0, 0) in component "04 | Straight forearm beam"
  circle A0 centre (0, 0) radius 15
  circle A1 centre (0, 0) radius 9
extrude "Output coupling sleeve | fastener detail pending (1)'" add sketch "Output coupling sleeve | fastener detail pending | profile (1) (2)" along normal blind 23 separate body makes body 125 in component "04 | Straight forearm beam"
ref_plane "WorkPlane34" through (0, 0, -8) normal (0, 0, 1) x (1, 0, 0) in component "04 | Straight forearm beam"
sketch "6001 independent wrist support outer race | profile" plane through (0, 0, -8) normal (0, 0, 1) x (1, 0, 0) in component "04 | Straight forearm beam"
  circle A0 centre (155, 0) radius 14
  circle A1 centre (155, 0) radius 13
extrude "6001 independent wrist support outer race" add sketch "6001 independent wrist support outer race | profile" along normal blind 8 separate body makes body 126 in component "04 | Straight forearm beam"
ref_plane "WorkPlane35" through (0, 0, -8) normal (0, 0, 1) x (1, 0, 0) in component "04 | Straight forearm beam"
sketch "6001 independent wrist support inner race | profile" plane through (0, 0, -8) normal (0, 0, 1) x (1, 0, 0) in component "04 | Straight forearm beam"
  circle A0 centre (155, 0) radius 7
  circle A1 centre (155, 0) radius 6
extrude "6001 independent wrist support inner race" add sketch "6001 independent wrist support inner race | profile" along normal blind 8 separate body makes body 127 in component "04 | Straight forearm beam"
ref_plane "WorkPlane36" through (0, 0, -7.85) normal (0, 0, 1) x (1, 0, 0) in component "04 | Straight forearm beam"
sketch "6001 independent wrist support shield | profile" plane through (0, 0, -7.85) normal (0, 0, 1) x (1, 0, 0) in component "04 | Straight forearm beam"
  circle A0 centre (155, 0) radius 13
  circle A1 centre (155, 0) radius 7
extrude "6001 independent wrist support shield" add sketch "6001 independent wrist support shield | profile" along normal blind 7.7 separate body makes body 128 in component "04 | Straight forearm beam"
ref_plane "WorkPlane37" through (0, 0, -8) normal (0, 0, 1) x (1, 0, 0) in component "04 | Straight forearm beam"
sketch "Wrist output spindle | profile" plane through (0, 0, -8) normal (0, 0, 1) x (1, 0, 0) in component "04 | Straight forearm beam"
  circle A0 centre (155, 0) radius 6
  circle A1 centre (155, 0) radius 2
extrude "Wrist output spindle" add sketch "Wrist output spindle | profile" along normal blind 39 separate body makes body 129 in component "04 | Straight forearm beam"
ref_plane "WorkPlane1" through (0, 0, -25) normal (0, 0, 1) x (1, 0, 0) in component "05 | MG996R gripper cassette"
sketch "MG996R palm cassette sidewall 0 | profile" plane through (0, 0, -25) normal (0, 0, 1) x (1, 0, 0) in component "05 | MG996R gripper cassette"
  line L0 (-16, -14) -> (67, -27)
  line L1 (67, -27) -> (67.1946, -24.5)
  line L2 (67.1946, -24.5) -> (-13.5, -11.8611)
  line L3 (-13.5, -11.8611) -> (-16, -14)
extrude "MG996R palm cassette sidewall 0" add sketch "MG996R palm cassette sidewall 0 | profile" along normal blind 56 separate body makes body 130 in component "05 | MG996R gripper cassette"
ref_plane "WorkPlane2" through (0, 0, -25) normal (0, 0, 1) x (1, 0, 0) in component "05 | MG996R gripper cassette"
sketch "MG996R palm cassette sidewall 1 | profile" plane through (0, 0, -25) normal (0, 0, 1) x (1, 0, 0) in component "05 | MG996R gripper cassette"
  line L0 (67, -27) -> (88, -27)
  line L1 (88, -27) -> (85.5, -24.5)
  line L2 (85.5, -24.5) -> (67.1946, -24.5)
  line L3 (67.1946, -24.5) -> (67, -27)
extrude "MG996R palm cassette sidewall 1" add sketch "MG996R palm cassette sidewall 1 | profile" along normal blind 56 separate body makes body 131 in component "05 | MG996R gripper cassette"
ref_plane "WorkPlane3" through (0, 0, -25) normal (0, 0, 1) x (1, 0, 0) in component "05 | MG996R gripper cassette"
sketch "MG996R palm cassette sidewall 3 | profile" plane through (0, 0, -25) normal (0, 0, 1) x (1, 0, 0) in component "05 | MG996R gripper cassette"
  line L0 (88, 27) -> (67, 27)
  line L1 (67, 27) -> (67.1946, 24.5)
  line L2 (67.1946, 24.5) -> (85.5, 24.5)
  line L3 (85.5, 24.5) -> (88, 27)
extrude "MG996R palm cassette sidewall 3" add sketch "MG996R palm cassette sidewall 3 | profile" along normal blind 56 separate body makes body 132 in component "05 | MG996R gripper cassette"
ref_plane "WorkPlane4" through (0, 0, -25) normal (0, 0, 1) x (1, 0, 0) in component "05 | MG996R gripper cassette"
sketch "MG996R palm cassette sidewall 4 | profile" plane through (0, 0, -25) normal (0, 0, 1) x (1, 0, 0) in component "05 | MG996R gripper cassette"
  line L0 (67, 27) -> (-16, 14)
  line L1 (-16, 14) -> (-13.5, 11.8611)
  line L2 (-13.5, 11.8611) -> (67.1946, 24.5)
  line L3 (67.1946, 24.5) -> (67, 27)
extrude "MG996R palm cassette sidewall 4" add sketch "MG996R palm cassette sidewall 4 | profile" along normal blind 56 separate body makes body 133 in component "05 | MG996R gripper cassette"
ref_plane "WorkPlane5" through (0, 0, -25) normal (0, 0, 1) x (1, 0, 0) in component "05 | MG996R gripper cassette"
sketch "MG996R palm cassette sidewall 5 | profile" plane through (0, 0, -25) normal (0, 0, 1) x (1, 0, 0) in component "05 | MG996R gripper cassette"
  line L0 (-16, 14) -> (-16, -14)
  line L1 (-16, -14) -> (-13.5, -11.8611)
  line L2 (-13.5, -11.8611) -> (-13.5, 11.8611)
  line L3 (-13.5, 11.8611) -> (-16, 14)
extrude "MG996R palm cassette sidewall 5" add sketch "MG996R palm cassette sidewall 5 | profile" along normal blind 56 separate body makes body 134 in component "05 | MG996R gripper cassette"
ref_plane "WorkPlane6" through (0, 0, -25) normal (0, 0, 1) x (1, 0, 0) in component "05 | MG996R gripper cassette"
sketch "Palm rear service panel | profile" plane through (0, 0, -25) normal (0, 0, 1) x (1, 0, 0) in component "05 | MG996R gripper cassette"
  line L0 (-16, -14) -> (67, -27)
  line L1 (67, -27) -> (88, -27)
  line L2 (88, -27) -> (88, 27)
  line L3 (88, 27) -> (67, 27)
  line L4 (67, 27) -> (-16, 14)
  line L5 (-16, 14) -> (-16, -14)
extrude "Palm rear service panel" add sketch "Palm rear service panel | profile" along normal blind 2.5 separate body makes body 135 in component "05 | MG996R gripper cassette"
ref_plane "WorkPlane7" through (0, 0, 28.5) normal (0, 0, 1) x (1, 0, 0) in component "05 | MG996R gripper cassette"
sketch "Flat Green Marble palm cover | profile" plane through (0, 0, 28.5) normal (0, 0, 1) x (1, 0, 0) in component "05 | MG996R gripper cassette"
  line L0 (-16, -14) -> (67, -27)
  line L1 (67, -27) -> (88, -27)
  line L2 (88, -27) -> (88, 27)
  line L3 (88, 27) -> (67, 27)
  line L4 (67, 27) -> (-16, 14)
  line L5 (-16, 14) -> (-16, -14)
extrude "Flat Green Marble palm cover" add sketch "Flat Green Marble palm cover | profile" along normal blind 2.5 separate body makes body 136 in component "05 | MG996R gripper cassette"
ref_plane "WorkPlane8" through (0, 0, 2.8) normal (0, 0, 1) x (1, 0, 0) in component "05 | MG996R gripper cassette"